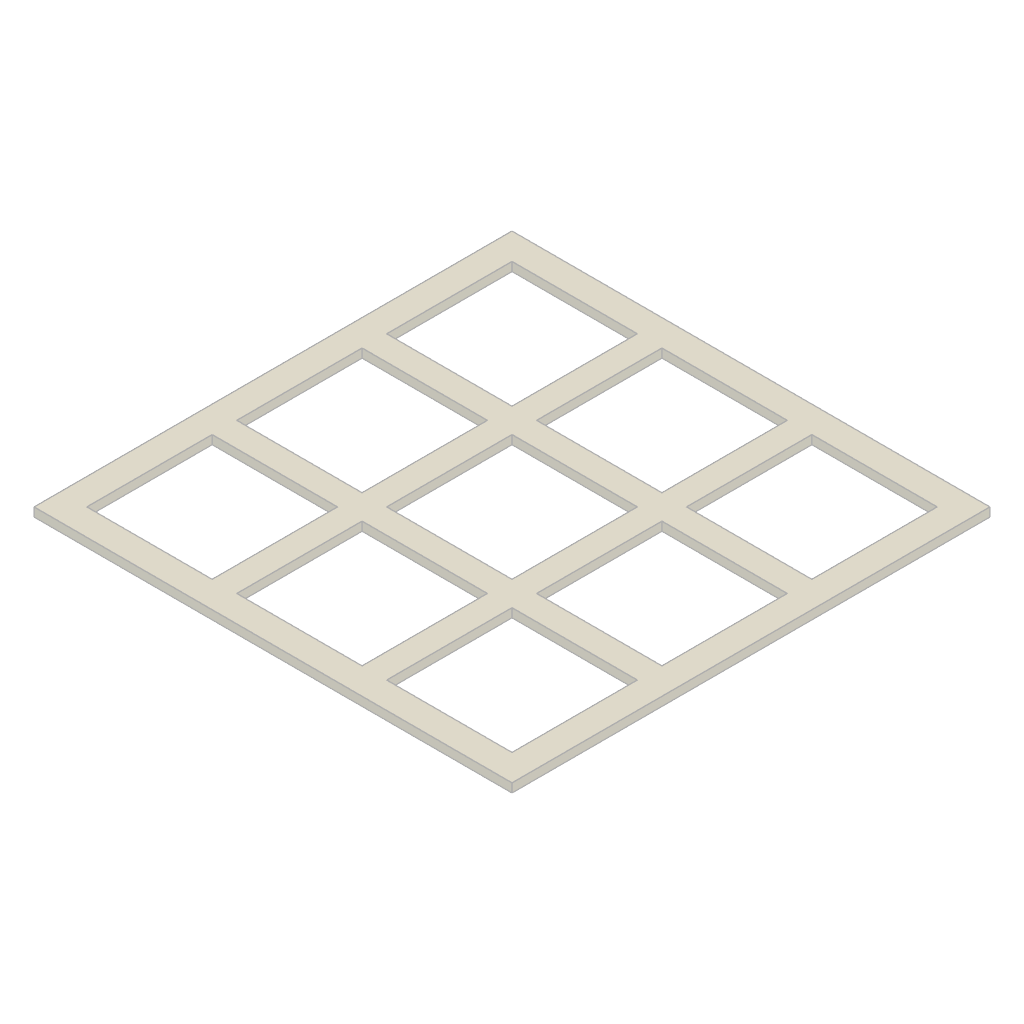
socket (Autodesk Fusion 360 design; units mm, degrees)
part number: 2026-10-06-00-32-47-322
Autodesk Fusion 360 part; units mm, degrees
sketch "Sketch1" plane through (0, 0, 0) normal (0, 1, 0) x (1, 0, 0)
  line L0 (0, 0) -> (14.2, 0)
  line L1 (14.2, 0) -> (14.2, 14.2)
  line L2 (14.2, 14.2) -> (0, 14.2)
  line L3 (0, 14.2) -> (0, 0)
  line L4 (17, 14.2) -> (17, 0)
  line L5 (31.2, 0) -> (31.2, 14.2)
  line L6 (17, 0) -> (31.2, 0)
  line L7 (31.2, 14.2) -> (17, 14.2)
  line L8 (34, 14.2) -> (34, 0)
  line L9 (48.2, 0) -> (48.2, 14.2)
  line L10 (34, 0) -> (48.2, 0)
  line L11 (48.2, 14.2) -> (34, 14.2)
  line L12 (0, 31.2) -> (0, 17)
  line L13 (14.2, 17) -> (14.2, 31.2)
  line L14 (0, 17) -> (14.2, 17)
  line L15 (14.2, 31.2) -> (0, 31.2)
  line L16 (17, 31.2) -> (17, 17)
  line L17 (31.2, 17) -> (31.2, 31.2)
  line L18 (17, 17) -> (31.2, 17)
  line L19 (31.2, 31.2) -> (17, 31.2)
  line L20 (34, 31.2) -> (34, 17)
  line L21 (48.2, 17) -> (48.2, 31.2)
  line L22 (34, 17) -> (48.2, 17)
  line L23 (48.2, 31.2) -> (34, 31.2)
  line L24 (0, 48.2) -> (0, 34)
  line L25 (14.2, 34) -> (14.2, 48.2)
  line L26 (0, 34) -> (14.2, 34)
  line L27 (14.2, 48.2) -> (0, 48.2)
  line L28 (17, 48.2) -> (17, 34)
  line L29 (31.2, 34) -> (31.2, 48.2)
  line L30 (17, 34) -> (31.2, 34)
  line L31 (31.2, 48.2) -> (17, 48.2)
  line L32 (34, 48.2) -> (34, 34)
  line L33 (48.2, 34) -> (48.2, 48.2)
  line L34 (34, 34) -> (48.2, 34)
  line L35 (48.2, 48.2) -> (34, 48.2)
  line L36 (-3, -3) -> (51.2, -3)
  line L37 (51.2, -3) -> (51.2, 51.2)
  line L38 (51.2, 51.2) -> (-3, 51.2)
  line L39 (-3, 51.2) -> (-3, -3)
  point P0 (17, 0)
  point P1 (34, 0)
  point P2 (0, 17)
  point P3 (17, 17)
  point P4 (34, 17)
  point P5 (0, 34)
  point P6 (17, 34)
  point P7 (34, 34)
  dimension "d1" = 14.2
  dimension "d2" = 14.2
  dimension "d5" = 17
  dimension "d6" = 17
  dimension "d7" = 3
  dimension "d8" = 3
  dimension "d9" = 3
  dimension "d10" = 3
  constraint horizontal L0
  constraint vertical L1
  constraint horizontal L2
  constraint vertical L3
  constraint coincident L0.start L3.end
  constraint horizontal L36
  constraint vertical L37
  constraint horizontal L38
  constraint vertical L39
  measures "d1" distance of L1.end L2.end
  measures "d2" distance of L0.end L1.end
  measures "d7" distance of L0 L36
  measures "d8" distance of L3 L39
  measures "d9" distance of L9 L37
  measures "d10" distance of L35 L38
extrude "Extrude1" add sketch "Sketch1" along normal blind 1
